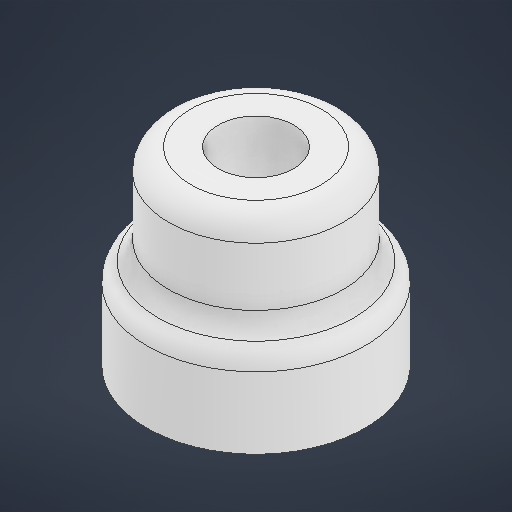
# Autodesk Inventor part: Адаптер_для_присоски
Saved by Autodesk Inventor 2026 (Build 300175050, 175E)
## iProperties
Created: 2026-10-25
Part Number: Адаптер_для_присоски
Material: Пластик АБС
Document SubType Name: Modeling
Designer: VK7
Density: 1.06 g/cm^3
Appearance: Гладкий — белый
Author: VK7
## iProperties of the stored document Адаптер_для_присоски_3DПЕЧАТЬ.ipt
Created: 2026-10-26
Part Number: Адаптер_для_присоски_3DПЕЧАТЬ
Material: Типовые
Document SubType Name: Modeling
Designer: VK7
Density: 1 g/cm^3
Appearance: По умолчанию
Author: VK7
Autodesk Inventor part; units mm, degrees
ref_plane "YZ Plane" through (0, 0, 0) normal (1, 0, 0) x (0, 1, 0)
ref_plane "XZ Plane" through (0, 0, 0) normal (0, 1, 0) x (-1, 0, 0)
ref_plane "XY Plane" through (0, 0, 0) normal (0, 0, 1) x (1, 0, 0)
sketch "Эскиз1" plane through (0, 0, 0) normal (0, 1, 0) x (-1, 0, 0)
  circle A0 centre (0, 0) radius 4.85
  circle A1 centre (0, 0) radius 7.5
  dimension "d0" = 9.7
  dimension "d1" = 15
  constraints: 2 centre point, 2 coincident
  measures "d0" diameter of A0
  measures "d1" diameter of A1
extrude "Выдавливание1" add sketch "Эскиз1" along normal blind 6
sketch "Эскиз2" plane through (0, 6, 0) normal (0, 1, 0) x (1, 0, 0)
  circle A0 centre (0, 0) radius 2.6
  circle A1 centre (0, 0) radius 6
  dimension "d6" = 5.2
  dimension "d7" = 12
  constraints: 2 centre point, 2 coincident
  measures "d6" diameter of A0
  measures "d7" diameter of A1
extrude "Выдавливание2" add sketch "Эскиз2" along normal blind 7
fillet "Сопряжение1" radius 1.5 2 edges at (-6, 6, 0) (7.5, 6, 0)
fillet "Сопряжение2" radius 1.5 1 edges at (-6, 13, 0)
sketch "Эскиз3" plane through (0, 6, 0) normal (0, -1, 0) x (1, 0, 0)
  circle A0 centre (0, 0) radius 1
  circle A1 centre (0, 0) radius 2.6 projected
  line L0 (0, 1) -> (-2.4, 1)
  line L1 (0, 1) -> (2.4, 1)
  line L2 (0, -1) -> (-2.4, -1)
  line L3 (0, -1) -> (2.4, -1)
  circle A2 centre (0, 0) radius 4.85 projected
  dimension "d12" = 2
  constraints: 8 end point, 6 point on circle, 2 point on line, 1 centre point, 1 coincident, 1 horizontal, 1 parallel
  measures "d12" diameter of A0
extrude "Выдавливание3" add sketch "Эскиз3" along normal blind 1 contours L0 A1 L1 | L3 A1 L2 | A2
